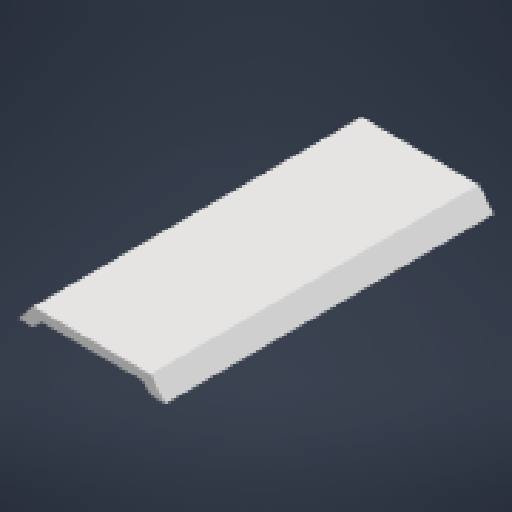
# Autodesk Inventor part: socle2
Saved by Autodesk Inventor 2026.1 (Build 301233020, 233B)
## iProperties
Created: 2025-11-26
Part Number: socle2
Material: Générique
Document SubType Name: Modeling
Designer: matpo
Density: 1 g/cm^3
Appearance: Par défaut
Author: matpo
Autodesk Inventor part; units mm, degrees
ref_plane "YZ Plane" through (0, 0, 0) normal (1, 0, 0) x (0, 1, 0)
sketch "Esquisse1" plane through (0, 0, 0) normal (0, 0, 1) x (1, 0, 0)
  line L0 (-28.1455, -22.1497) -> (-21.7176, -22.1497) projected
  line L1 (-28.1455, -22.1497) -> (-21.7176, -14.4892) projected
  line L2 (-21.7176, -22.1497) -> (-18.6461, -18.4892) projected
  line L3 (-18.6461, -18.4892) -> (25.2109, -18.4892) projected
  line L4 (-21.7176, -14.4892) -> (28.2824, -14.4892) projected
  line L5 (25.2109, -18.4892) -> (28.2824, -22.1497) projected
  line L6 (34.7103, -22.1497) -> (28.2824, -22.1497) projected
  line L7 (28.2824, -14.4892) -> (34.7103, -22.1497) projected
  point P0 (0, 0)
ref_plane "Plan de construction1" through (-6.5827, 4.1497, 80) normal (0, 0, 1) x (1, 0, 0)
ref_plane "Plan de construction2" through (-6.5827, 4.1497, 80) normal (0, 0, 1) x (1, 0, 0)
extrude "Extrusion1" add sketch "Esquisse1" along normal up to surface (80 mm away)
